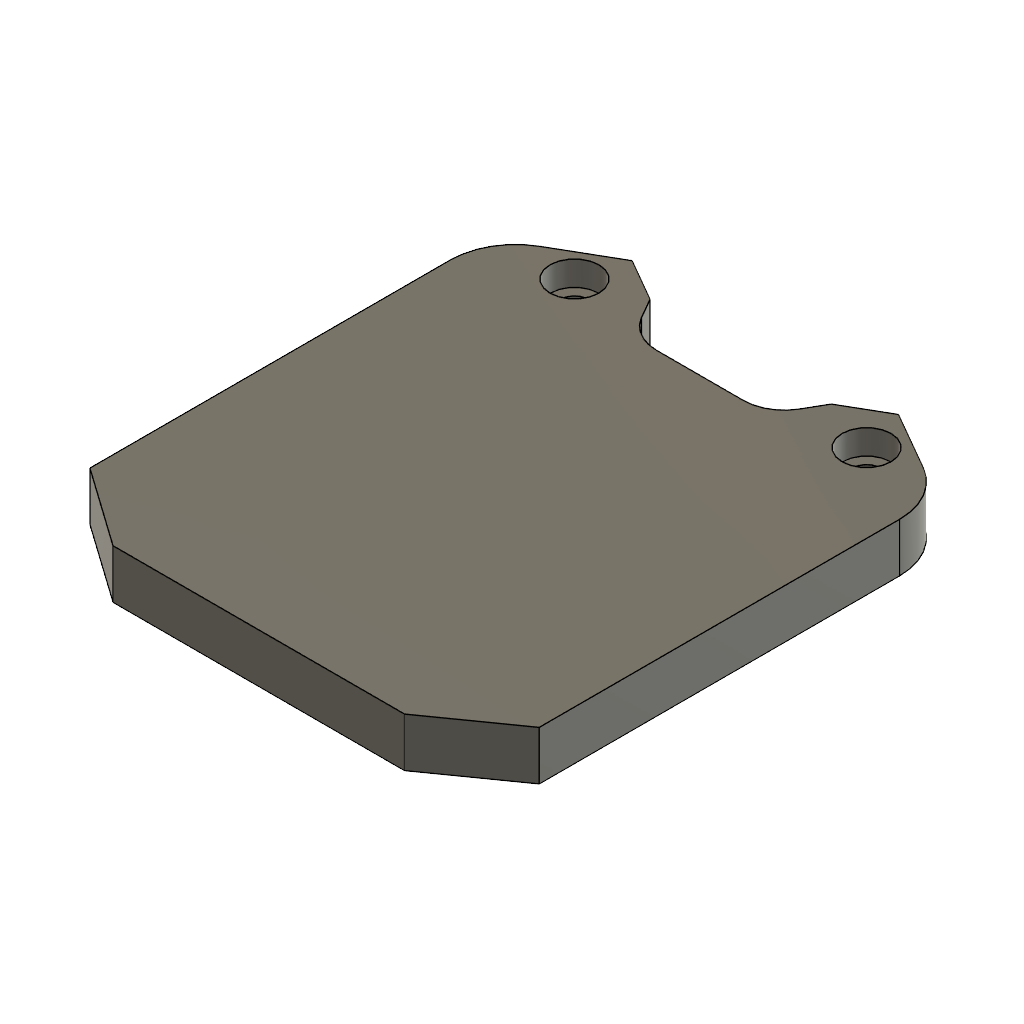
replica_backplate (Autodesk Fusion 360 design; units mm, degrees)
part number: 2026-11-10-15-27-35-513
Autodesk Fusion 360 part; units mm, degrees
ref_plane "WorkPlane1" through (0, 20, 0) normal (0, 1, 0) x (0, 0, 1)
sketch "body" plane through (0, 20, 0) normal (0, 1, 0) x (1, 0, 0)
  line L0 (-23.5, -19.05) -> (-17.8431, -23.05)
  line L1 (-17.8431, -23.05) -> (17.8431, -23.05)
  line L2 (17.8431, -23.05) -> (23.5, -19.05)
  circle A0 centre (-12.5, -17.05) radius 1.75
  circle A1 centre (12.5, -17.05) radius 1.75
  circle A2 centre (17.88, 33.4774) radius 2.25 construction
  line L3 (27.5, 26.95) -> (27.5, 27.8763)
  arc A3 (27.5, 27.8763) -> (23.4918, 34.8092) centre (19.5, 27.8763) ccw
  line L4 (23.4918, 34.8092) -> (16.3, 38.95)
  line L5 (16.3, 38.95) -> (11.0964, 35.9457)
  line L6 (27.5, 26.95) -> (27.5, -16.2216)
  line L7 (27.5, -16.2216) -> (17.8431, -23.05)
  line L8 (9.6624, 33.4551) -> (11.0964, 35.9457)
  arc A4 (5.3293, 30.95) -> (9.6624, 33.4551) centre (5.3293, 35.95) ccw
  line L9 (-5.3293, 30.95) -> (5.3293, 30.95)
  circle A5 centre (17.88, 33.4774) radius 1.7
  circle A6 centre (17.88, 33.4774) radius 3
  circle A7 centre (12.5, -17.05) radius 2.25
  line L10 (0, -1.75) -> (0, -22.5) construction
  line L11 (-27.5, 26.95) -> (-27.5, -16.2216)
  line L12 (-27.5, -16.2216) -> (-17.8431, -23.05)
  line L13 (-27.5, 26.95) -> (-27.5, 27.8763)
  line L14 (-23.4918, 34.8092) -> (-16.3, 38.95)
  line L15 (-16.3, 38.95) -> (-11.0964, 35.9457)
  arc A8 (-23.4918, 34.8092) -> (-27.5, 27.8763) centre (-19.5, 27.8763) ccw
  line L16 (5.3293, 30.95) -> (-5.3293, 30.95)
  arc A9 (-9.6624, 33.4551) -> (-5.3293, 30.95) centre (-5.3293, 35.95) ccw
  line L17 (-9.6624, 33.4551) -> (-11.0964, 35.9457)
  circle A10 centre (-12.5, -17.05) radius 2.25
  circle A11 centre (-17.88, 33.4774) radius 1.7
  circle A12 centre (-17.88, 33.4774) radius 3
  line L18 (-22.5929, -18.05) -> (-22.5929, -14.05)
  line L19 (-20.9929, -14.05) -> (-20.9929, -18.05)
  line L20 (22.5929, -18.05) -> (20.9929, -18.05)
  line L21 (20.9929, -18.05) -> (20.9929, -14.05)
  line L22 (20.9929, -14.05) -> (22.5929, -14.05)
  line L23 (22.5929, -14.05) -> (22.5929, -18.05)
extrude "Extrusion1" add sketch "body" along normal blind 6 contours L0 L1 L2 L3 A3 L4 L5 L6 L7 L8 A4 L9 L11 L12 L13 L14 L15 A8 L16 A9 L17 | A0 | A1 | A6 | A7 | A10 | A12 | L20 L21 L22 L23
extrude "Extrusion2" cut sketch "body" against normal blind 3 from surface at 6 contours A5 | A6 | A11 | A12
extrude "Extrusion3" cut sketch "body" along normal blind 4.5 contours A0 | A1 | A7 | A10
equation "hotend_length = 54 mm" comment "Lenght of the uhf hotend for the uhf cowls. Default: 54mm  (Pheatus dragon UHF alike)"
equation "hotend_screwhole_radius = 8.1 mm" comment "Radius of the mounting screholes. Default: 8,10mm (pheatus dragon alike)"
equation "hotend_diameter = 22.2 mm" comment "Diameter of the kotend heatsink. Default: 22,20mm (pheatus dragon alike)"
equation "DS_adapter_lenght = 35.75 mm" comment "Lenght or depth of the DraftShift adapter. Default: 35,75m"
equation "extruder_screwholes_right = 17.5 mm" comment "Right extruder screwhole, distance from center. Orbiter:  17,5 Sherpa_mini:  21,75 Sherpa_micro:  18.05"
equation "extruder_screwholes_left = 19.5 mm" comment "Left extruder screwhole, distance from center. Orbiter:  16,5 Sherpa_mini:  21,75 Sherpa_micro:  13,95"
equation "heat_insert_diameter = 4.5 mm" comment "Diameter of the M3 heated inserts holes, Default: 4.5mm"
